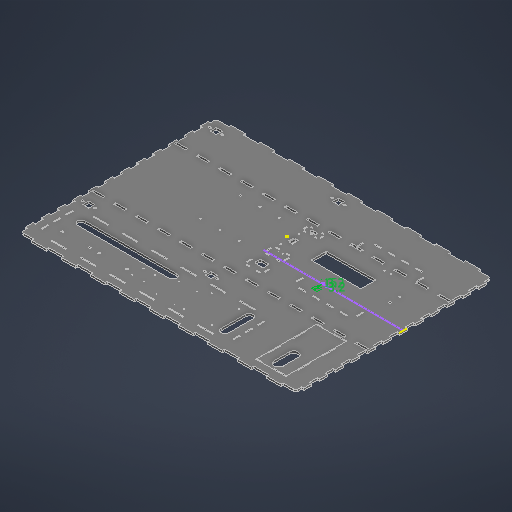
# Autodesk Inventor part: UpperBase
Saved by Autodesk Inventor 2027.1 (Build 311270010, 270A)
## iProperties
Created: 2026-09-29
Part Number: UpperBase
Material: MDF Medium Density Fiberboard
Document SubType Name: Modeling
Designer: SDS Scholar
Density: 0.8 g/cm^3
Appearance: Gray
Mass: 3254.36 g
Surface Area: 12239.4 cm^2
Volume: 4067.95 cm^3
Author: SDS Scholar
Autodesk Inventor part; units mm, degrees
(part 1 of 3)
ref_plane "YZ Plane" through (0, 0, 0) normal (1, 0, 0) x (0, 1, 0)
ref_plane "XZ Plane" through (0, 0, 0) normal (0, 1, 0) x (-1, 0, 0)
ref_plane "XY Plane" through (0, 0, 0) normal (0, 0, 1) x (1, 0, 0)
sketch "Sketch1" plane through (0, 0, 0) normal (0, 1, 0) x (-1, 0, 0)
  line L0 (456, 226) -> (-456, 226)
  line L1 (-456, 226) -> (-456, -226)
  line L2 (-456, -226) -> (456, -226)
  line L3 (456, -226) -> (456, 226)
  line L4 (0, 226) -> (0, -226) construction
  line L5 (456, 0) -> (-456, 0) construction
  line L6 (426, -196) -> (406, -196)
  line L7 (406, -196) -> (406, -176)
  line L8 (406, -176) -> (426, -176)
  line L9 (426, -176) -> (426, -196)
  line L10 (-24, -226) -> (-24, 226)
  line L11 (397.5, -186) -> (394.5, -186) construction
  line L12 (397.5, -183.1) -> (394.5, -183.1)
  line L13 (394.5, -188.9) -> (397.5, -188.9)
  arc A0 (397.5, -188.9) -> (397.5, -183.1) centre (397.5, -186) ccw
  arc A1 (394.5, -183.1) -> (394.5, -188.9) centre (394.5, -186) ccw
  line L14 (416, -196) -> (416, -176) construction
  line L15 (434.5, -186) -> (437.5, -186) construction
  line L16 (434.5, -183.1) -> (437.5, -183.1)
  line L17 (437.5, -188.9) -> (434.5, -188.9)
  arc A2 (434.5, -183.1) -> (434.5, -188.9) centre (434.5, -186) ccw
  arc A3 (437.5, -188.9) -> (437.5, -183.1) centre (437.5, -186) ccw
  line L18 (426, -186) -> (406, -186) construction
  line L19 (130, 226) -> (130, -226) construction
  line L20 (-24, -90) -> (126, -90)
  line L21 (126, -90) -> (126, 90)
  line L22 (126, 90) -> (-24, 90)
  line L23 (-24, 90) -> (-24, -90)
  circle A4 centre (41, 0) radius 25
  circle A5 centre (-34, 0) radius 25
  line L24 (456, 226) -> (-456, 226)
  line L25 (-456, 226) -> (-456, 426)
  line L26 (-456, 426) -> (456, 426)
  line L27 (456, 426) -> (456, 226)
  arc A6 (425.75, -196) -> (426, -195.75) centre (425.75, -195.75) ccw
  arc A7 (406, -195.75) -> (406.25, -196) centre (406.25, -195.75) ccw
  arc A8 (426, -176.25) -> (425.75, -176) centre (425.75, -176.25) ccw
  arc A9 (406.25, -176) -> (406, -176.25) centre (406.25, -176.25) ccw
  line L28 (406, 221) -> (406, 241)
  line L29 (406, 241) -> (426, 241)
  line L30 (426, 241) -> (426, 221)
  line L31 (397.5, 231) -> (394.5, 231) construction
  line L32 (397.5, 233.9) -> (394.5, 233.9)
  line L33 (394.5, 228.1) -> (397.5, 228.1)
  arc A10 (397.5, 228.1) -> (397.5, 233.9) centre (397.5, 231) ccw
  arc A11 (394.5, 233.9) -> (394.5, 228.1) centre (394.5, 231) ccw
  line L34 (416, 221) -> (416, 241) construction
  line L35 (426, 231) -> (406, 231) construction
  arc A12 (406.25, 241) -> (406, 240.75) centre (406.25, 240.75) ccw
  arc A13 (406, 221.25) -> (406.25, 221) centre (406.25, 221.25) ccw
  arc A14 (426, 240.75) -> (425.75, 241) centre (425.75, 240.75) ccw
  arc A15 (425.75, 221) -> (426, 221.25) centre (425.75, 221.25) ccw
  line L36 (434.5, 233.9) -> (437.5, 233.9)
  arc A16 (434.5, 233.9) -> (434.5, 228.1) centre (434.5, 231) ccw
  line L37 (434.5, 231) -> (437.5, 231) construction
  line L38 (437.5, 228.1) -> (434.5, 228.1)
  arc A17 (437.5, 228.1) -> (437.5, 233.9) centre (437.5, 231) ccw
  line L39 (426, 221) -> (406, 221)
  line L40 (6, -196) -> (6, -176)
  line L41 (6, -176) -> (26, -176)
  line L42 (26, -176) -> (26, -196)
  line L43 (-2.5, -186) -> (-5.5, -186) construction
  line L44 (-2.5, -183.1) -> (-5.5, -183.1)
  line L45 (-5.5, -188.9) -> (-2.5, -188.9)
  arc A18 (-2.5, -188.9) -> (-2.5, -183.1) centre (-2.5, -186) ccw
  arc A19 (-5.5, -183.1) -> (-5.5, -188.9) centre (-5.5, -186) ccw
  line L46 (16, -196) -> (16, -176) construction
  line L47 (26, -186) -> (6, -186) construction
  arc A20 (6.25, -176) -> (6, -176.25) centre (6.25, -176.25) ccw
  arc A21 (6, -195.75) -> (6.25, -196) centre (6.25, -195.75) ccw
  arc A22 (26, -176.25) -> (25.75, -176) centre (25.75, -176.25) ccw
  arc A23 (25.75, -196) -> (26, -195.75) centre (25.75, -195.75) ccw
  line L48 (34.5, -183.1) -> (37.5, -183.1)
  arc A24 (34.5, -183.1) -> (34.5, -188.9) centre (34.5, -186) ccw
  line L49 (34.5, -186) -> (37.5, -186) construction
  line L50 (37.5, -188.9) -> (34.5, -188.9)
  arc A25 (37.5, -188.9) -> (37.5, -183.1) centre (37.5, -186) ccw
  line L51 (26, -196) -> (6, -196)
  line L52 (6, 221) -> (6, 241)
  line L53 (6, 241) -> (26, 241)
  line L54 (26, 241) -> (26, 221)
  line L55 (-2.5, 231) -> (-5.5, 231) construction
  line L56 (-2.5, 233.9) -> (-5.5, 233.9)
  line L57 (-5.5, 228.1) -> (-2.5, 228.1)
  arc A26 (-2.5, 228.1) -> (-2.5, 233.9) centre (-2.5, 231) ccw
  arc A27 (-5.5, 233.9) -> (-5.5, 228.1) centre (-5.5, 231) ccw
  line L58 (16, 221) -> (16, 241) construction
  line L59 (26, 231) -> (6, 231) construction
  arc A28 (6.25, 241) -> (6, 240.75) centre (6.25, 240.75) ccw
  arc A29 (6, 221.25) -> (6.25, 221) centre (6.25, 221.25) ccw
  arc A30 (26, 240.75) -> (25.75, 241) centre (25.75, 240.75) ccw
  arc A31 (25.75, 221) -> (26, 221.25) centre (25.75, 221.25) ccw
  line L60 (34.5, 233.9) -> (37.5, 233.9)
  arc A32 (34.5, 233.9) -> (34.5, 228.1) centre (34.5, 231) ccw
  line L61 (34.5, 231) -> (37.5, 231) construction
  line L62 (37.5, 228.1) -> (34.5, 228.1)
  arc A33 (37.5, 228.1) -> (37.5, 233.9) centre (37.5, 231) ccw
  line L63 (26, 221) -> (6, 221)
  line L64 (426, 396) -> (-204, 396)
  line L65 (-204, 396) -> (-204, 256)
  line L66 (-204, 256) -> (426, 256)
  line L67 (426, 256) -> (426, 396)
  line L68 (423, 393) -> (-201, 393)
  line L69 (-201, 393) -> (-201, 259)
  line L70 (-201, 259) -> (423, 259)
  line L71 (423, 259) -> (423, 393)
  line L72 (-396, 396) -> (-296, 396)
  line L73 (-296, 396) -> (-296, 196)
  line L74 (-296, 196) -> (-396, 196)
  line L75 (-396, 196) -> (-396, 396)
  line L76 (-299, 199) -> (-299, 393)
  line L77 (-299, 393) -> (-393, 393)
  line L78 (-393, 393) -> (-393, 199)
  line L79 (-393, 199) -> (-299, 199)
  circle A34 centre (-115, 0) radius 2.5
  circle A35 centre (-258, 0) radius 2.5
  line L80 (-34, 25) -> (-34, -25) construction
  line L81 (-4, 45) -> (-64, 45)
  line L82 (-64, 45) -> (-64, 145)
  line L83 (-64, 145) -> (-4, 145)
  line L84 (-4, 145) -> (-4, 45)
  line L85 (-4, 142) -> (-64, 142) construction
  line L86 (-7, 145) -> (-7, 45) construction
  line L87 (-61, 145) -> (-61, 45) construction
  line L88 (-34, 45) -> (-34, 145) construction
  line L89 (-4, 95) -> (-64, 95) construction
  line L90 (-26.5, 45) -> (-41.5, 45)
  line L91 (-41.5, 45) -> (-41.5, 48)
  line L92 (-41.5, 48) -> (-26.5, 48)
  line L93 (-26.5, 48) -> (-26.5, 45)
  line L94 (-26.5, 48) -> (-7, 48) construction
  line L95 (-11.75, 45) -> (-21.75, 45)
  line L96 (-21.75, 45) -> (-21.75, 48)
  line L97 (-21.75, 48) -> (-11.75, 48)
  line L98 (-11.75, 48) -> (-11.75, 45)
  line L99 (-4, 78) -> (-61, 78) construction
  line L100 (-4, 81) -> (-61, 81) construction
  line L101 (-11.75, 78) -> (-21.75, 78)
  line L102 (-21.75, 78) -> (-21.75, 81)
  line L103 (-21.75, 81) -> (-11.75, 81)
  line L104 (-11.75, 81) -> (-11.75, 78)
  line L105 (-11.75, 142) -> (-21.75, 142)
  line L106 (-21.75, 142) -> (-21.75, 145)
  line L107 (-21.75, 145) -> (-11.75, 145)
  line L108 (-11.75, 145) -> (-11.75, 142)
  line L109 (-4, 55.5) -> (-7, 55.5)
  line L110 (-7, 55.5) -> (-7, 70.5)
  line L111 (-7, 70.5) -> (-4, 70.5)
  line L112 (-4, 70.5) -> (-4, 55.5)
  line L113 (-7, 45) -> (-7, 145) construction
  line L114 (-4, 134.5) -> (-7, 134.5)
  line L115 (-7, 134.5) -> (-7, 119.5)
  line L116 (-7, 119.5) -> (-4, 119.5)
  line L117 (-46.25, 45) -> (-46.25, 48)
  line L118 (-46.25, 48) -> (-56.25, 48)
  line L119 (-56.25, 48) -> (-56.25, 45)
  line L120 (-56.25, 78) -> (-46.25, 78)
  line L121 (-46.25, 78) -> (-46.25, 81)
  line L122 (-46.25, 81) -> (-56.25, 81)
  line L123 (-56.25, 81) -> (-56.25, 78)
  line L124 (-56.25, 142) -> (-46.25, 142)
  line L125 (-46.25, 142) -> (-46.25, 145)
  line L126 (-56.25, 145) -> (-56.25, 142)
  line L127 (-64, 55.5) -> (-61, 55.5)
  line L128 (-61, 55.5) -> (-61, 70.5)
  line L129 (-61, 70.5) -> (-64, 70.5)
  line L130 (-61, 119.5) -> (-64, 119.5)
  line L131 (-61, 134.5) -> (-61, 119.5)
  line L132 (-64, 134.5) -> (-61, 134.5)
  line L133 (-24, 125) -> (-44, 125)
  line L134 (-49, 120) -> (-49, 110)
  line L135 (-44, 105) -> (-24, 105)
  line L136 (-19, 110) -> (-19, 120)
  arc A36 (-19, 120) -> (-24, 125) centre (-24, 120) ccw
  arc A37 (-24, 105) -> (-19, 110) centre (-24, 110) ccw
  arc A38 (-49, 110) -> (-44, 105) centre (-44, 110) ccw
  arc A39 (-44, 125) -> (-49, 120) centre (-44, 120) ccw
  line L137 (-6, -45) -> (-62, -45)
  line L138 (-62, -45) -> (-62, -71)
  line L139 (-62, -71) -> (-6, -71)
  line L140 (-6, -71) -> (-6, -45)
  line L141 (-3, -45) -> (-59, -45)
  line L142 (-59, -45) -> (-59, -71)
  line L143 (-59, -71) -> (-3, -71)
  line L144 (-3, -71) -> (-3, -45)
  line L145 (-59, -53) -> (-56, -53)
  line L146 (-56, -53) -> (-56, -63)
  line L147 (-56, -63) -> (-59, -63)
  line L148 (-59, -63) -> (-59, -53)
  line L149 (-31, -45) -> (-31, -71) construction
  line L150 (-51.5, -45) -> (-46.5, -45)
  line L151 (-46.5, -45) -> (-46.5, -48)
  line L152 (-46.5, -48) -> (-51.5, -48)
  line L153 (-51.5, -48) -> (-51.5, -45)
  line L154 (-46.5, -71) -> (-51.5, -71)
  line L155 (-51.5, -71) -> (-51.5, -68)
  line L156 (-51.5, -68) -> (-46.5, -68)
  line L157 (-46.5, -68) -> (-46.5, -71)
  line L158 (-15.5, -45) -> (-15.5, -48)
  line L159 (-15.5, -48) -> (-10.5, -48)
  line L160 (-10.5, -48) -> (-10.5, -45)
  line L161 (-15.5, -68) -> (-15.5, -71)
  line L162 (-10.5, -68) -> (-15.5, -68)
  line L163 (-10.5, -71) -> (-10.5, -68)
  line L164 (-6, -63) -> (-3, -63)
  line L165 (-3, -53) -> (-6, -53)
  line L166 (-6, -53) -> (-6, -63)
  line L167 (-34, -71) -> (-34, -45) construction
  line L168 (-25, -62) -> (-37, -62)
  line L169 (-37, -54) -> (-25, -54)
  arc A40 (-25, -62) -> (-21, -58) centre (-25, -58) ccw
  arc A41 (-21, -58) -> (-25, -54) centre (-25, -58) ccw
  arc A42 (-37, -54) -> (-41, -58) centre (-37, -58) ccw
  arc A43 (-41, -58) -> (-37, -62) centre (-37, -58) ccw
  circle A44 centre (-27.09, 53.5) radius 1.25
  circle A45 centre (-40.91, 53.5) radius 1.25
  line L170 (-29, -51) -> (-33, -51)
  line L171 (-33, -51) -> (-33, -48)
  line L172 (-33, -48) -> (-29, -48)
  line L173 (-29, -48) -> (-29, -51)
  circle A46 centre (193, 88) radius 2.5
  circle A47 centre (193, -43) radius 2.5
  circle A48 centre (130, 88) radius 2.5
  circle A49 centre (130, -43) radius 2.5
  circle A50 centre (67, 88) radius 2.5
  circle A51 centre (67, -43) radius 2.5
  line L174 (193, 88) -> (193, -43) construction
  line L175 (416, 231) -> (416, -186) construction
  line L176 (-115, 0) -> (-131, 0) construction
  line L177 (-115, 10) -> (-242, 10)
  line L178 (-242, -10) -> (-115, -10)
  arc A52 (-115, -10) -> (-115, 10) centre (-115, 0) ccw
  arc A53 (-131, 10) -> (-131, -10) centre (-131, 0) ccw
  line L179 (-258, 0) -> (-242, 0) construction
  line L180 (-258, -10) -> (-242, -10)
  line L181 (-242, 10) -> (-258, 10)
  arc A54 (-258, 10) -> (-258, -10) centre (-258, 0) ccw
  arc A55 (-242, -10) -> (-242, 10) centre (-242, 0) ccw
  line L182 (423, 259) -> (375, 259)
  line L183 (375, 259) -> (375, 256)
  line L184 (375, 256) -> (423, 256)
  line L185 (423, 256) -> (423, 259)
  line L186 (327, 259) -> (327, 256)
  line L187 (279, 259) -> (279, 256)
  line L188 (231, 259) -> (231, 256)
  line L189 (183, 259) -> (183, 256)
  line L190 (135, 259) -> (135, 256)
  line L191 (87, 259) -> (87, 256)
  line L192 (39, 259) -> (39, 256)
  line L193 (-9, 259) -> (-9, 256)
  line L194 (-57, 259) -> (-57, 256)
  line L195 (-105, 259) -> (-105, 256)
  line L196 (-153, 259) -> (-153, 256)
  line L197 (-201, 259) -> (-201, 256)
  line L198 (-201, 393) -> (-153, 393)
  line L199 (-153, 393) -> (-153, 396)
  line L200 (-153, 396) -> (-201, 396)
  line L201 (-201, 396) -> (-201, 393)
  line L202 (-105, 393) -> (-105, 396)
  line L203 (-57, 393) -> (-57, 396)
  line L204 (-9, 393) -> (-9, 396)
  line L205 (39, 393) -> (39, 396)
  line L206 (87, 393) -> (87, 396)
  line L207 (135, 393) -> (135, 396)
  line L208 (426, 396) -> (423, 396)
  line L209 (423, 396) -> (423, 376)
  line L210 (423, 376) -> (426, 376)
  line L211 (426, 376) -> (426, 396)
  line L212 (423, 356) -> (426, 356)
  line L213 (423, 336) -> (426, 336)
  line L214 (423, 316) -> (426, 316)
  line L215 (423, 296) -> (426, 296)
  line L216 (423, 276) -> (426, 276)
  line L217 (423, 256) -> (426, 256)
  line L218 (-204, 396) -> (-201, 396)
  line L219 (-201, 396) -> (-201, 376)
  line L220 (-201, 376) -> (-204, 376)
  line L221 (-204, 376) -> (-204, 396)
  line L222 (-201, 356) -> (-204, 356)
  line L223 (-201, 336) -> (-204, 336)
  line L224 (-201, 316) -> (-204, 316)
  line L225 (-201, 296) -> (-204, 296)
  line L226 (-201, 276) -> (-204, 276)
  line L227 (-201, 256) -> (-204, 256)
  line L228 (183, 393) -> (183, 396)
  line L229 (231, 393) -> (231, 396)
  line L230 (279, 393) -> (279, 396)
  line L231 (327, 393) -> (327, 396)
  line L232 (375, 393) -> (375, 396)
  line L233 (423, 393) -> (423, 396)
  line L234 (-393.0285, 198.9955) -> (-299.0285, 198.9955)
  line L235 (-296.0285, 195.9955) -> (-396.0285, 195.9955)
  line L236 (-296.0285, 395.9955) -> (-296.0285, 195.9955)
  line L237 (-299.0285, 198.9955) -> (-299.0285, 392.9955)
  line L238 (-396.0285, 195.9955) -> (-396.0285, 395.9955)
  line L239 (-393.0285, 392.9955) -> (-393.0285, 198.9955)
  line L240 (-299.0285, 392.9955) -> (-393.0285, 392.9955)
  line L241 (-396.0285, 395.9955) -> (-296.0285, 395.9955)
  line L242 (-396.0285, 195.9955) -> (-393.0285, 195.9955)
  line L243 (-393.0285, 195.9955) -> (-393.0285, 236.2955)
  line L244 (-393.0285, 236.2955) -> (-396.0285, 236.2955)
  line L245 (-396.0285, 236.2955) -> (-396.0285, 195.9955)
  line L246 (-393.0285, 236.2955) -> (-396.0285, 236.2955)
  line L247 (-396.0285, 236.2955) -> (-396.0285, 276.2955)
  line L248 (-396.0285, 276.2955) -> (-393.0285, 276.2955)
  line L249 (-393.0285, 276.2955) -> (-393.0285, 236.2955)
  line L250 (-393.0285, 276.2955) -> (-396.0285, 276.2955)
  line L251 (-396.0285, 276.2955) -> (-396.0285, 316.5955)
  line L252 (-396.0285, 316.5955) -> (-393.0285, 316.5955)
  line L253 (-393.0285, 316.5955) -> (-393.0285, 276.2955)
  line L254 (-393.0285, 316.5955) -> (-396.0285, 316.5955)
  line L255 (-396.0285, 316.5955) -> (-396.0285, 356.5955)
  line L256 (-396.0285, 356.5955) -> (-393.0285, 356.5955)
  line L257 (-393.0285, 356.5955) -> (-393.0285, 316.5955)
  line L258 (-393.0285, 356.5955) -> (-396.0285, 356.5955)
  line L259 (-396.0285, 356.5955) -> (-396.0285, 395.9955)
  line L260 (-396.0285, 395.9955) -> (-393.0285, 395.9955)
  line L261 (-393.0285, 395.9955) -> (-393.0285, 356.5955)
  line L262 (-393.0285, 395.9955) -> (-353.0285, 395.9955)
  line L263 (-353.0285, 395.9955) -> (-353.0285, 392.9955)
  line L264 (-353.0285, 392.9955) -> (-393.0285, 392.9955)
  line L265 (-393.0285, 392.9955) -> (-393.0285, 395.9955)
  line L266 (-353.0285, 392.9955) -> (-312.7285, 392.9955)
  line L267 (-312.7285, 392.9955) -> (-312.7285, 395.9955)
  line L268 (-312.7285, 395.9955) -> (-353.0285, 395.9955)
  line L269 (-353.0285, 395.9955) -> (-353.0285, 392.9955)
  line L270 (-299.0285, 392.9955) -> (-312.7285, 392.9955)
  line L271 (-312.7285, 392.9955) -> (-312.7285, 395.9955)
  line L272 (-312.7285, 395.9955) -> (-299.0285, 395.9955)
  line L273 (-299.0285, 395.9955) -> (-299.0285, 392.9955)
  line L274 (-296.0285, 395.9955) -> (-299.0285, 395.9955)
  line L275 (-299.0285, 395.9955) -> (-299.0285, 355.6955)
  line L276 (-296.0285, 355.6955) -> (-296.0285, 395.9955)
  line L277 (-296.0285, 195.9955) -> (-299.0285, 195.9955)
  line L278 (-299.0285, 195.9955) -> (-299.0285, 236.2955)
  line L279 (-299.0285, 236.2955) -> (-296.0285, 236.2955)
  line L280 (-296.0285, 236.2955) -> (-296.0285, 195.9955)
  line L281 (-296.0285, 236.2955) -> (-299.0285, 236.2955)
  line L282 (-299.0285, 236.2955) -> (-299.0285, 276.2955)
  line L283 (-299.0285, 276.2955) -> (-296.0285, 276.2955)
  line L284 (-296.0285, 276.2955) -> (-296.0285, 236.2955)
  line L285 (-296.0285, 276.2955) -> (-299.0285, 276.2955)
  line L286 (-299.0285, 276.2955) -> (-299.0285, 316.5955)
  line L287 (-299.0285, 316.5955) -> (-296.0285, 316.5955)
  line L288 (-296.0285, 316.5955) -> (-296.0285, 276.2955)
  line L289 (-296.0285, 316.5955) -> (-299.0285, 316.5955)
  line L290 (-299.0285, 316.5955) -> (-299.0285, 356.5955)
  line L291 (-299.0285, 356.5955) -> (-296.0285, 356.5955)
  line L292 (-296.0285, 356.5955) -> (-296.0285, 316.5955)
  line L293 (-393.0285, 195.9955) -> (-353.0285, 195.9955)
  line L294 (-353.0285, 195.9955) -> (-353.0285, 198.9955)
  line L295 (-353.0285, 198.9955) -> (-393.0285, 198.9955)
  line L296 (-393.0285, 198.9955) -> (-393.0285, 195.9955)
  line L297 (-353.0285, 198.9955) -> (-312.7285, 198.9955)
  line L298 (-312.7285, 198.9955) -> (-312.7285, 195.9955)
  line L299 (-312.7285, 195.9955) -> (-353.0285, 195.9955)
  line L300 (-353.0285, 195.9955) -> (-353.0285, 198.9955)
  point P0 (0, 0)
  point P1 (-24, 0)
  point P2 (396, -186)
  point P3 (436, -186)
  point P4 (130, 0)
  point P5 (126, 0)
  point P6 (0, 0)
  point P7 (-456, 226)
  point P8 (396, 231)
  point P9 (436, 231)
  point P10 (-4, -186)
  point P11 (16, -186)
  point P12 (36, -186)
  point P13 (-4, 231)
  point P14 (16, 231)
  point P15 (36, 231)
  point P16 (6.25, 221)
  point P17 (25.75, 241)
  point P18 (6.25, 241)
  point P19 (6.25, -196)
  point P20 (25.75, -176)
  point P21 (6.25, -176)
  point P22 (-396, 226)
  point P23 (-393, 226)
  point P24 (-299, 226)
  point P25 (-296, 226)
  point P26 (-284.8127, -574.8692)
  point P27 (-284.8127, -584.8692)
  point P28 (-284.8127, -612.3692)
  point P29 (-284.8127, -622.3692)
  point P30 (-274.3127, -631.6192)
  point P31 (-274.3127, -628.6192)
  point P32 (-259.3127, -628.6192)
  point P33 (-259.3127, -631.6192)
  point P34 (-210.3127, -631.6192)
  point P35 (-210.3127, -628.6192)
  point P36 (-195.3127, -628.6192)
  point P37 (-195.3127, -631.6192)
  point P38 (-184.8127, -622.3692)
  point P39 (-184.8127, -612.3692)
  point P40 (-184.8127, -584.8692)
  point P41 (-184.8127, -574.8692)
  point P42 (-195.3127, -565.6192)
  point P43 (-195.3127, -568.6192)
  point P44 (-210.3127, -568.6192)
  point P45 (-210.3127, -565.6192)
  point P46 (-259.3127, -565.6192)
  point P47 (-259.3127, -568.6192)
  point P48 (-274.3127, -568.6192)
  point P49 (-274.3127, -565.6192)
  point P50 (-34, 95)
  point P51 (-34, 48)
  point P52 (-34, 95)
  point P53 (-16.75, 48)
  point P54 (-16.75, 48)
  point P55 (-16.75, 78)
  point P56 (-16.75, 142)
  point P57 (-4, 63)
  point P58 (-4, 119.5)
  point P59 (-4, 134.5)
  point P60 (-64, 134.5)
  point P61 (-64, 119.5)
  point P62 (-46.25, 145)
  point P63 (-56.25, 145)
  point P64 (-11.75, 145)
  point P65 (-64, 70.5)
  point P66 (-64, 55.5)
  point P67 (-4, 70.5)
  point P68 (-21.75, 45)
  point P69 (-56.25, 45)
  point P70 (-46.25, 45)
  point P71 (-19, 125)
  point P72 (-49, 105)
  point P73 (-19, 105)
  point P74 (-34, 105)
  point P75 (-3, -58)
  point P76 (-56, -58)
  point P77 (-59, -58)
  point P78 (-49, -48)
  point P79 (-49, -68)
  point P80 (-292.5225, -73.6896)
  point P81 (-285.0225, -81.6896)
  point P82 (-249.0225, -81.6896)
  point P83 (-244.0225, -81.6896)
  point P84 (-236.5225, -73.6896)
  point P85 (-236.5225, -63.6896)
  point P86 (-244.0225, -55.6896)
  point P87 (-249.0225, -55.6896)
  point P88 (-280.0225, -55.6896)
  point P89 (-46.5, -45)
  point P90 (-51.5, -45)
  point P91 (-234, -46)
  point P92 (-234, -56)
  point P93 (-51.5, -71)
  point P94 (-46.5, -71)
  point P95 (-10.5, -45)
  point P96 (-15.5, -45)
  point P97 (-6, -63)
  point P98 (-6, -53)
  point P99 (-15.5, -71)
  point P100 (-10.5, -71)
  point P101 (-21, -62)
  point P102 (-41, -54)
  point P103 (-21, -54)
  point P104 (-6, -58)
  point P105 (-31, -54)
  point P106 (-21, -58)
  point P107 (-31, -48)
  point P108 (-34, -58)
  point P109 (-31, -58)
  point P110 (-6, -58)
  point P111 (-31, -51)
  point P112 (-3, -53)
  point P113 (-3, -63)
  point P114 (416, 22.5)
  point P115 (193, 22.5)
  point P116 (-123, 0)
  point P117 (-250, 0)
  point P118 (-396, 395.9955)
  point P119 (-396, 356.5955)
  point P120 (-396, 316.5955)
  point P121 (-396, 276.2955)
  point P122 (-396, 236.2955)
  point P123 (-393.0285, 196)
  point P124 (-353.0285, 196)
  point P125 (-312.7285, 196)
  point P126 (-299.0285, 196)
  point P127 (-299.0285, 199)
  point P128 (-353.0285, 393)
  point P129 (-312.7285, 393)
  point P130 (-299.0285, 393)
  point P131 (-299, 356.5955)
  point P132 (-299, 316.5955)
  point P133 (-299, 276.2955)
  point P134 (-299, 236.2955)
  point P135 (-296.0285, 196)
  dimension "d1" = 912
  dimension "d15" = 20
  dimension "d16" = 20
  dimension "d17" = 30
  dimension "d18" = 30
  dimension "d26" = 1.5
  dimension "d27" = 5.8
  dimension "d28" = 8.5
  dimension "d51" = 480
  dimension "d52" = 326
  dimension "d72" = 150
  dimension "d73" = 180
  dimension "d74" = 50
  dimension "d75" = 85
  dimension "d78" = 50
  dimension "d79" = 75
  dimension "d80" = 652
  dimension "d81" = 200
  dimension "d82" = 912
  dimension "d85" = 0.25
  dimension "d88" = 417
  dimension "d91" = 400
  dimension "d94" = 140
  dimension "d95" = 630
  dimension "d96" = 30
  dimension "d97" = 30
  dimension "d98" = 3
  dimension "d104" = 200
  dimension "d105" = 100
  dimension "d106" = 30
  dimension "d107" = 60
  dimension "d108" = 3
  dimension "d110" = 81
  dimension "d111" = 5
  dimension "d112" = 5
  dimension "d119" = 100
  dimension "d120" = 60
  dimension "d121" = 45
  dimension "d123" = 3
  dimension "d124" = 3
  dimension "d125" = 3
  dimension "d151" = 3
  dimension "d152" = 15
  dimension "d153" = 10
  dimension "d154" = 3
  dimension "d155" = 30
  dimension "d156" = 10
  dimension "d157" = 10
  dimension "d158" = 15
  dimension "d159" = 18
  dimension "d160" = 30
  dimension "d161" = 20
  dimension "d162" = 20
  dimension "d163" = 5
  dimension "d164" = 56
  dimension "d165" = 26
  dimension "d166" = 90
  dimension "d167" = 56
  dimension "d168" = 26
  dimension "d169" = 10
  dimension "d170" = 3
  dimension "d171" = 5
  dimension "d172" = 3
  dimension "d173" = 10
  constraints: 622 end point, 90 point on circle, 87 parallel, 71 point on line, 56 centre point, 55 symmetric about line, 49 perpendicular, 48 midpoint, 45 horizontal, 26 tangent, 8 vertical, 8 vertical alignment, 7 horizontal alignment, 6 equal radius, 1 coincident, 308 other
  measures "d1" distance of L1.end L2.end
  measures "d15" distance of L7.end L8.end
  measures "d16" distance of L6.end L7.end
  measures "d17" distance between parallel lines of L2 L6
  measures "d18" distance between parallel lines of L3 L9
  measures "d26" distance of point (396, -186) L11.end
  measures "d27" diameter of A1
  measures "d28" distance from line of L7 L11.start
  measures "d51" distance between parallel lines of L3 L10
  measures "d52" distance between parallel lines of L3 L19
  measures "d72" distance of L21.end L22.end
  measures "d73" distance of L20.end L21.end
  measures "d74" diameter of A4
  measures "d75" distance from line of L21 A4.centre
  measures "d78" diameter of A5
  measures "d79" distance of A5.centre A4.centre
  measures "d80" distance between parallel lines of L26 L2
  measures "d81" distance between parallel lines of L26 L0
  measures "d82" distance of L25.end L26.end
  measures "d85" radius of A6
  measures "d88" distance of L7.end L28.end
  measures "d91" distance of L7.end L40.end
  measures "d94" distance of L66.end L64.start
  measures "d95" distance of L65.end L66.end
  measures "d96" distance between parallel lines of L26 L64
  measures "d97" distance between parallel lines of L27 L67
  measures "d98" distance between parallel lines of L67 L71
  measures "d104" distance of L72.end L73.end
  measures "d105" distance of L73.end L74.end
  measures "d106" distance between parallel lines of L26 L72
  measures "d107" distance between parallel lines of L25 L75
  measures "d108" distance between parallel lines of L73 L76
  measures "d110" distance of A5.centre L176.start
  measures "d111" diameter of A34
  measures "d112" diameter of A35
  measures "d119" distance of L83.end L81.start
  measures "d120" distance of L81.start L81.end
  measures "d121" distance from line of L81 A5.centre
  measures "d123" distance between parallel lines of L84 L86
  measures "d124" distance between parallel lines of L83 L85
  measures "d125" distance between parallel lines of L82 L87
  measures "d151" distance of L92.end L90.start
  measures "d152" distance of L91.end L92.end
  measures "d153" distance of L96.end L97.end
  measures "d154" distance between parallel lines of L99 L100
  measures "d155" distance between parallel lines of L94 L99
  measures "d156" distance of L101.start L101.end
  measures "d157" distance of L105.start L105.end
  measures "d158" distance of L109.end L110.end
  measures "d159" distance from line of L81 point (-4, 63)
  measures "d160" distance of point (-49, 105) point (-19, 105)
  measures "d161" distance of point (-19, 105) point (-19, 125)
  measures "d162" distance between parallel lines of L133 L83
  measures "d163" radius of A36
  measures "d164" distance of L137.start L137.end
  measures "d165" distance of L137.end L138.end
  measures "d166" distance between parallel lines of L81 L137
  measures "d167" distance of L141.start L141.end
  measures "d168" distance of L141.end L142.end
  measures "d169" distance of L145.end L146.end
  measures "d170" distance of L145.start L145.end
  measures "d171" distance of L151.end L152.end
  measures "d172" distance of L152.end L150.start
  measures "d173" distance from line of L142 point (-49, -48)
extrude "Extrusion1" add sketch "Sketch1" along normal blind 7 contours L3 L2 L10 L20 L21 L22 A50 L84 L83 L0 L52 L63 L54 L28 L39 L30 | L0 L30 L29 L28 L54 L53 L52 L73 L72 L75 L241 L238 L25 L26 L27 | L30 A15 L39 A13 L28 L0 | L0 L28 A12 L29 A14 L30 | A14 L29 L30 | L30 L39 A15 | L2 L1 L0 L238 L235 L236 L74 L73 L10 L83 L82 L81 A5 L137 L138 L139 | L54 A31 L63 A29 L52 L0 | L0 L52 A28 L53 A30 L54 | A13 L39 L28 | L28 L29 A12 | L10 L139 L143 L144 L141 L137 A5 L81 L84 L22 A50 L21 L20 | A30 L53 L54 | L54 L63 A31 | L139 L157 L156 L155 L142 L147 L146 L145 L137 L153 L152 L151 L10 A41 L169 A42 A43 L168 A40 | L10 A40 A41 L137 L158 L159 L160 L140 L139 L163 L162 L161 | L238 L244 L75 L0 | L0 L75 L74 L243 L235 L238 | A29 L63 L52 | L52 L53 A28 | A40 L168 A43 A42 L169 A41 L10 | L10 A41 A40 | L139 L155 L156 L157 | L161 L162 L163 L139 | L75 L244 L239 L0 | L0 L239 L243 L74 L75 | L238 L248 L75 L244 | L73 L74 L236 L0 | L0 L236 L241 L75 L72 L73 | L83 L106 L105 L108 L84 L114 L115 L116 L22 L10 A37 L136 A36 | L10 L133 A39 L134 A38 L135 L81 L93 L92 L91 L117 L118 L119 L82 L127 L128 L129 L130 L131 L132 L83 L126 L124 L125 | A50 L22 | L22 A50 | L239 L240 L78 L0 | L0 L78 L79 L237 L234 L239 | L75 L248 L239 L244 | L243 L74 L294 L235 | L238 L252 L75 L248 | L236 L74 L278 L237 L79 L76 L0 | L0 L76 L279 L236 | A36 L136 A37 L10 | L10 L135 A38 L134 A39 L133 | L125 L124 L126 L83 | L83 L108 L105 L106 | L139 L138 L137 L142 | L140 L164 L144 L143 | L78 L240 L237 L0 | L0 L237 L79 L78 | L234 L294 L74 L243 | L75 L252 L239 L248 | L294 L74 L298 L235 | L238 L256 L75 L252 | L76 L79 L237 L0 | L0 L237 L279 L76 | L279 L76 L283 L236 | L236 L235 L278 L74 | A5 L10 | L10 A5 | L137 L160 L159 L158 | L151 L152 L153 L137 | L142 L145 L146 L147 | L140 L165 L144 L164 | L84 L111 L110 L109 L81 L98 L97 L96 L10 L22 | L240 L261 L241 L263 L77 L78 | L78 L77 L263 L240 | L234 L298 L74 L294 | L75 L256 L239 L252 | L298 L74 L278 L235 | L238 L241 L75 L256 | L279 L237 L283 L76 | L283 L76 L287 L236 | L74 L298 L234 L278 | L241 L261 L239 L256 L75 | L140 L141 L144 L165 | L116 L115 L114 L84 | L84 L109 L110 L111 | L263 L77 L267 L240 | L283 L237 L287 L76 | L287 L76 L291 L236 | L132 L131 L130 L82 | L263 L241 L267 L77 | L267 L77 L273 L240 | L287 L237 L291 L76 | L96 L97 L98 L81 | L81 L91 L92 L93 | L267 L241 L273 L77 | L273 L77 L76 L291 L237 | L76 L77 L273 L241 L236 L291 | L129 L128 L127 L82 | L81 L119 L118 L117 | L6 A6 L9 | L6 A7 L7 A9 L8 A8 L9 A6 | L6 L7 A7 | A8 L8 L9 | L7 L8 A9 | A0 L13 A1 L12 | L16 A3 L17 A2 | A4 | A10 L33 A11 L32 | L36 A17 L38 A16 | L40 A21 L51 | L40 A20 L41 A22 L42 A23 L51 A21 | L40 L41 A20 | A23 L42 L51 | L41 L42 A22 | A18 L45 A19 L44 | L48 A25 L50 A24 | A26 L57 A27 L56 | L60 A33 L62 A32 | L67 L210 L71 L209 L64 | L209 L68 L232 L64 | L67 L212 L71 L210 | L232 L68 L231 L64 | L71 L70 L69 L68 | L67 L213 L71 L212 | L231 L68 L230 L64 | L67 L214 L71 L213 | L230 L68 L229 L64 | L67 L215 L71 L214 | L229 L68 L228 L64 | L67 L216 L71 L215 | L228 L68 L207 L64 | L67 L66 L185 L71 L216 | L207 L68 L206 L64 | L206 L68 L205 L64 | L66 L183 L70 L185 | L205 L68 L204 L64 | L66 L186 L70 L183 | L204 L68 L203 L64 | L66 L187 L70 L186 | L203 L68 L202 L64 | L66 L188 L70 L187 | L202 L68 L199 L64 | L66 L189 L70 L188 | L199 L68 L201 L64 | L66 L190 L70 L189 | L201 L69 L220 L65 L64 | L66 L191 L70 L190 | L66 L192 L70 L191 | L220 L69 L222 L65 | L66 L193 L70 L192 | L222 L69 L223 L65 | L66 L194 L70 L193 | L223 L69 L224 L65 | L66 L195 L70 L194 | L224 L69 L225 L65 | L66 L196 L70 L195 | L225 L69 L226 L65 | L66 L197 L70 L196 | L226 L69 L197 L66 L65 | A34 | A35 | L101 L102 L103 L104 | L123 L122 L121 L120 | A44 | A45 | L170 L171 L172 L173 | A46 | A47 | A48 | A49 | A51 | A52 L178 A53 L177 | A53 L178 A55 L177 | A55 L180 A54 L181
extrude "Extrusion2" cut sketch "Sketch1" along normal blind 7 contours L30 A15 L39 A13 L28 L0 | L0 L28 A12 L29 A14 L30 | L54 A31 L63 A29 L52 L0 | L0 L52 A28 L53 A30 L54 | A40 L168 A43 A42 L169 A41 L10 | L10 A41 A40 | L139 L155 L156 L157 | L161 L162 L163 L139 | L73 L74 L236 L0 | L0 L236 L241 L75 L72 L73 | A50 L22 | L22 A50 | L239 L240 L78 L0 | L0 L78 L79 L237 L234 L239 | L75 L248 L239 L244 | A36 L136 A37 L10 | L10 L135 A38 L134 A39 L133 | L125 L124 L126 L83 | L83 L108 L105 L106 | L234 L294 L74 L243 | L279 L76 L283 L236 | L137 L160 L159 L158 | L151 L152 L153 L137 | L142 L145 L146 L147 | L140 L165 L144 L164 | L240 L261 L241 L263 L77 L78 | L75 L256 L239 L252 | L74 L298 L234 L278 | L116 L115 L114 L84 | L84 L109 L110 L111 | L287 L76 L291 L236 | L132 L131 L130 L82 | L96 L97 L98 L81 | L267 L241 L273 L77 | L129 L128 L127 L82 | L81 L119 L118 L117 | L6 A7 L7 A9 L8 A8 L9 A6 | A0 L13 A1 L12 | L16 A3 L17 A2 | A10 L33 A11 L32 | L36 A17 L38 A16 | L40 A20 L41 A22 L42 A23 L51 A21 | A18 L45 A19 L44 | L48 A25 L50 A24 | A26 L57 A27 L56 | L60 A33 L62 A32 | L67 L212 L71 L210 | L232 L68 L231 L64 | L67 L214 L71 L213 | L230 L68 L229 L64 | L67 L216 L71 L215 | L228 L68 L207 L64 | L206 L68 L205 L64 | L66 L186 L70 L183 | L204 L68 L203 L64 | L66 L188 L70 L187 | L202 L68 L199 L64 | L66 L190 L70 L189 | L66 L192 L70 L191 | L220 L69 L222 L65 | L66 L194 L70 L193 | L223 L69 L224 L65 | L66 L196 L70 L195 | L225 L69 L226 L65 | A34 | A35 | L101 L102 L103 L104 | L123 L122 L121 L120 | A44 | A45 | L170 L171 L172 L173 | A46 | A47 | A48 | A49 | A51 | A52 L178 A53 L177 | A53 L178 A55 L177 | A55 L180 A54 L181
fillet "Fillet1" radius 7 4 edges at (456, 3.5, 426) (456, 3.5, -226) (-456, 3.5, -226) (-456, 3.5, 426)
sketch "Sketch2" plane through (0, 7, 0) normal (0, 1, 0) x (1, 0, 0)
  line L0 (456, -419) -> (456, 219) projected
  line L1 (456, 16) -> (354.8, 16)
  line L2 (354.8, 16) -> (354.8, -16)
  line L3 (354.8, -16) -> (456, -16)
  line L4 (456, -16) -> (456, 16)
  line L5 (306.8, 0) -> (356.4612, 0)
  circle A0 centre (354.8, -16) radius 2.9
  circle A1 centre (354.8, 16) radius 2.9
  circle A2 centre (162.2, -16) radius 2.9
  circle A3 centre (162.2, 16) radius 2.9
  point P0 (0, 0)
  point P1 (354.8, 0)
  dimension "d205" = 101.2
  dimension "d206" = 32
  dimension "d208" = 5.8
  dimension "d209" = 5.8
  dimension "d212" = 192.6
  dimension "d403" = 48
  dimension "d404" = 203
  dimension "d405" = 99.5388
  constraints: 10 end point, 4 centre point, 3 horizontal, 2 coincident, 2 parallel, 2 point on line, 1 midpoint, 1 perpendicular, 4 other
  measures "d205" distance of L3.end L2.end
  measures "d206" distance of L2.end L1.end
  measures "d208" diameter of A0
  measures "d209" diameter of A1
  measures "d212" distance of A0.centre A2.centre
  measures "d403" distance from line of L5.start L2
  measures "d404" distance from line of L0.end L1
  measures "d405" distance from line of L5.end L0
extrude "Extrusion4" cut sketch "Sketch2" against normal through all contours A0 L2 L3 | L3 L2 A0 | A1 L2 L1 | L1 L2 A1 | A2 | A3
sketch "Sketch3" plane through (0, 7, 0) normal (0, 1, 0) x (1, 0, 0)
  line L0 (344.7411, -371) -> (344.7411, -321) construction
  line L1 (359.7411, -371) -> (359.7411, -321)
  line L2 (329.7411, -321) -> (329.7411, -371)
  arc A0 (329.7411, -371) -> (359.7411, -371) centre (344.7411, -371) ccw
  arc A1 (359.7411, -321) -> (329.7411, -321) centre (344.7411, -321) ccw
  line L3 (-449, -426) -> (449, -426) projected
  point P0 (0, 0)
  point P1 (344.7411, -346)
  dimension "d408" = 50
  dimension "d409" = 80
  dimension "d410" = 15
  constraints: 8 end point, 4 point on circle, 4 tangent, 2 centre point, 1 midpoint, 1 parallel, 1 vertical
  measures "d408" distance of L0.start L0.end
  measures "d409" distance from line of L3 point (344.741, -346)
  measures "d410" radius of A0
extrude "Extrusion5" cut sketch "Sketch3" against normal through all
sketch "Sketch4" plane through (0, 7, 0) normal (0, 1, 0) x (1, 0, 0)
  line L0 (258, -10) -> (115, -10) projected
  line L1 (115, 10) -> (258, 10) projected
  arc A0 (258, -10) -> (258, 10) centre (258, 0) ccw projected
  arc A1 (115, 10) -> (115, -10) centre (115, 0) ccw projected
  line L2 (107, -25) -> (266, -25)
  line L3 (268, -23) -> (268, 23)
  line L4 (266, 25) -> (107, 25)
  line L5 (105, 23) -> (105, -23)
  line L6 (105, -25) -> (268, 25) construction
  line L7 (268, -25) -> (105, 25) construction
  arc A2 (105, -23) -> (107, -25) centre (107, -23) ccw
  arc A3 (107, 25) -> (105, 23) centre (107, 23) ccw
  arc A4 (266, -25) -> (268, -23) centre (266, -23) ccw
  arc A5 (268, 23) -> (266, 25) centre (266, 23) ccw
  point P0 (0, 0)
  point P1 (186.5, 0)
  point P2 (186.5, 0)
  point P3 (186.5, 10)
  point P4 (105, 0)
  dimension "d411" = 50
  dimension "d412" = 163
  dimension "d415" = 2
  constraints: 12 end point, 9 point on circle, 8 point on line, 8 tangent, 5 midpoint, 4 centre point, 3 equal radius, 2 parallel, 1 perpendicular, 1 vertical alignment
  measures "d411" distance of L6.end L7.start
  measures "d412" distance of L6.end L7.end
  measures "d415" radius of A2
extrude "Extrusion6" cut sketch "Sketch4" against normal blind 10
sketch "Sketch5" plane through (0, 7, 0) normal (0, 1, 0) x (1, 0, 0)
  line L0 (105, -23) -> (105, 23) projected
  arc A0 (107, 25) -> (105, 23) centre (107, 23) ccw projected
  line L1 (107, 25) -> (266, 25) projected
  arc A1 (268, 23) -> (266, 25) centre (266, 23) ccw projected
  line L2 (268, 23) -> (268, -23) projected
  arc A2 (266, -25) -> (268, -23) centre (266, -23) ccw projected
  line L3 (266, -25) -> (107, -25) projected
  arc A3 (105, -23) -> (107, -25) centre (107, -23) ccw projected
  circle A4 centre (354.8, 16) radius 2.9 projected
  circle A5 centre (354.8, -16) radius 2.9 projected
  arc A6 (-456, -419) -> (-449, -426) centre (-449, -419) ccw projected
  line L4 (-449, -426) -> (449, -426) projected
  arc A7 (449, -426) -> (456, -419) centre (449, -419) ccw projected
  line L5 (456, -419) -> (456, 219) projected
  arc A8 (456, 219) -> (449, 226) centre (449, 219) ccw projected
  line L6 (449, 226) -> (-449, 226) projected
  arc A9 (-449, 226) -> (-456, 219) centre (-449, 219) ccw projected
  line L7 (-456, 219) -> (-456, -419) projected
  line L8 (201, -276) -> (204, -276) projected
  line L9 (204, -276) -> (204, -296) projected
  line L10 (204, -296) -> (201, -296) projected
  line L11 (201, -296) -> (201, -276) projected
  line L12 (-426, -316) -> (-423, -316) projected
  line L13 (-423, -316) -> (-423, -336) projected
  line L14 (-423, -336) -> (-426, -336) projected
  line L15 (-426, -336) -> (-426, -316) projected
  line L16 (9, -396) -> (9, -393) projected
  line L17 (9, -393) -> (57, -393) projected
  line L18 (57, -393) -> (57, -396) projected
  line L19 (57, -396) -> (9, -396) projected
  line L20 (-39, -256) -> (-39, -259) projected
  line L21 (-39, -259) -> (-87, -259) projected
  line L22 (-87, -259) -> (-87, -256) projected
  line L23 (-87, -256) -> (-39, -256) projected
  circle A10 centre (-67, 43) radius 2.5 projected
  circle A11 centre (-130, 43) radius 2.5 projected
  line L24 (51.5, 68) -> (46.5, 68) projected
  line L25 (46.5, 68) -> (46.5, 71) projected
  line L26 (46.5, 71) -> (51.5, 71) projected
  line L27 (51.5, 71) -> (51.5, 68) projected
  line L28 (6, 53) -> (3, 53) projected
  line L29 (3, 53) -> (3, 63) projected
  line L30 (3, 63) -> (6, 63) projected
  line L31 (6, 63) -> (6, 53) projected
  line L32 (56.25, -48) -> (46.25, -48) projected
  line L33 (46.25, -48) -> (46.25, -45) projected
  line L34 (46.25, -45) -> (56.25, -45) projected
  line L35 (56.25, -45) -> (56.25, -48) projected
  line L36 (46.25, -81) -> (46.25, -78) projected
  line L37 (46.25, -78) -> (56.25, -78) projected
  line L38 (56.25, -78) -> (56.25, -81) projected
  line L39 (56.25, -81) -> (46.25, -81) projected
  line L40 (61, -134.5) -> (61, -119.5) projected
  line L41 (61, -119.5) -> (64, -119.5) projected
  line L42 (64, -119.5) -> (64, -134.5) projected
  line L43 (64, -134.5) -> (61, -134.5) projected
  arc A12 (-406.25, 176) -> (-406, 176.25) centre (-406.25, 176.25) ccw projected
  line L44 (-406.25, 176) -> (-425.75, 176) projected
  arc A13 (-426, 176.25) -> (-425.75, 176) centre (-425.75, 176.25) ccw projected
  line L45 (-426, 176.25) -> (-426, 195.75) projected
  arc A14 (-425.75, 196) -> (-426, 195.75) centre (-425.75, 195.75) ccw projected
  line L46 (-425.75, 196) -> (-406.25, 196) projected
  arc A15 (-406, 195.75) -> (-406.25, 196) centre (-406.25, 195.75) ccw projected
  line L47 (-406, 195.75) -> (-406, 176.25) projected
  line L48 (-25.75, 196) -> (-6.25, 196) projected
  arc A16 (-6, 195.75) -> (-6.25, 196) centre (-6.25, 195.75) ccw projected
  line L49 (-6, 195.75) -> (-6, 176.25) projected
  arc A17 (-6.25, 176) -> (-6, 176.25) centre (-6.25, 176.25) ccw projected
  line L50 (-6.25, 176) -> (-25.75, 176) projected
  arc A18 (-26, 176.25) -> (-25.75, 176) centre (-25.75, 176.25) ccw projected
  line L51 (-26, 176.25) -> (-26, 195.75) projected
  arc A19 (-25.75, 196) -> (-26, 195.75) centre (-25.75, 195.75) ccw projected
  line L52 (5.5, -233.9) -> (2.5, -233.9) projected
  arc A20 (2.5, -228.1) -> (2.5, -233.9) centre (2.5, -231) ccw projected
  line L53 (2.5, -228.1) -> (5.5, -228.1) projected
  arc A21 (5.5, -233.9) -> (5.5, -228.1) centre (5.5, -231) ccw projected
  line L54 (-394.5, 183.1) -> (-397.5, 183.1) projected
  arc A22 (-397.5, 188.9) -> (-397.5, 183.1) centre (-397.5, 186) ccw projected
  line L55 (-397.5, 188.9) -> (-394.5, 188.9) projected
  arc A23 (-394.5, 183.1) -> (-394.5, 188.9) centre (-394.5, 186) ccw projected
  line L56 (-25.75, -221) -> (-6.25, -221) projected
  arc A24 (-6, -221.25) -> (-6.25, -221) centre (-6.25, -221.25) ccw projected
  line L57 (-6, -221.25) -> (-6, -240.75) projected
  arc A25 (-6.25, -241) -> (-6, -240.75) centre (-6.25, -240.75) ccw projected
  line L58 (-6.25, -241) -> (-25.75, -241) projected
  arc A26 (-26, -240.75) -> (-25.75, -241) centre (-25.75, -240.75) ccw projected
  line L59 (-26, -240.75) -> (-26, -221.25) projected
  arc A27 (-25.75, -221) -> (-26, -221.25) centre (-25.75, -221.25) ccw projected
  line L60 (-394.5, -233.9) -> (-397.5, -233.9) projected
  arc A28 (-397.5, -228.1) -> (-397.5, -233.9) centre (-397.5, -231) ccw projected
  line L61 (-397.5, -228.1) -> (-394.5, -228.1) projected
  arc A29 (-394.5, -233.9) -> (-394.5, -228.1) centre (-394.5, -231) ccw projected
  line L62 (296, -196) -> (296.0285, -196) projected
  line L63 (396, -236.2955) -> (396, -276.2955) projected
  line L64 (396, -396) -> (296, -396) projected
  line L65 (296, -396) -> (296, -196) projected
  line L66 (46.25, -142) -> (56.25, -142) projected
  line L67 (56.25, -142) -> (56.25, -145) projected
  line L68 (56.25, -145) -> (46.25, -145) projected
  line L69 (46.25, -145) -> (46.25, -142) projected
  line L70 (61, -70.5) -> (61, -55.5) projected
  line L71 (61, -55.5) -> (64, -55.5) projected
  line L72 (64, -55.5) -> (64, -70.5) projected
  line L73 (64, -70.5) -> (61, -70.5) projected
  arc A30 (49, -110) -> (44, -105) centre (44, -110) ccw projected
  line L74 (49, -110) -> (49, -120) projected
  arc A31 (44, -125) -> (49, -120) centre (44, -120) ccw projected
  line L75 (44, -125) -> (24, -125) projected
  arc A32 (19, -120) -> (24, -125) centre (24, -120) ccw projected
  line L76 (19, -120) -> (19, -110) projected
  arc A33 (24, -105) -> (19, -110) centre (24, -110) ccw projected
  line L77 (24, -105) -> (44, -105) projected
  line L78 (56, 53) -> (56, 63) projected
  line L79 (56, 63) -> (59, 63) projected
  line L80 (59, 63) -> (59, 53) projected
  line L81 (59, 53) -> (56, 53) projected
  line L82 (25, 62) -> (37, 62) projected
  arc A34 (37, 54) -> (37, 62) centre (37, 58) ccw projected
  line L83 (37, 54) -> (25, 54) projected
  arc A35 (25, 62) -> (25, 54) centre (25, 58) ccw projected
  circle A36 centre (-193, 43) radius 2.5 projected
  circle A37 centre (-67, -88) radius 2.5 projected
  line L84 (-135, -256) -> (-135, -259) projected
  line L85 (-135, -259) -> (-183, -259) projected
  line L86 (-183, -259) -> (-183, -256) projected
  line L87 (-183, -256) -> (-135, -256) projected
  line L88 (105, -396) -> (105, -393) projected
  line L89 (105, -393) -> (153, -393) projected
  line L90 (153, -393) -> (153, -396) projected
  line L91 (153, -396) -> (105, -396) projected
  line L92 (-426, -356) -> (-423, -356) projected
  line L93 (-423, -356) -> (-423, -376) projected
  line L94 (-423, -376) -> (-426, -376) projected
  line L95 (-426, -376) -> (-426, -356) projected
  line L96 (201, -316) -> (204, -316) projected
  line L97 (204, -316) -> (204, -336) projected
  line L98 (204, -336) -> (201, -336) projected
  line L99 (201, -336) -> (201, -316) projected
  line L100 (-279, -396) -> (-279, -393) projected
  line L101 (-279, -393) -> (-231, -393) projected
  line L102 (-231, -393) -> (-231, -396) projected
  line L103 (-231, -396) -> (-279, -396) projected
  line L104 (-426, -276) -> (-423, -276) projected
  line L105 (-423, -276) -> (-423, -296) projected
  line L106 (-423, -296) -> (-426, -296) projected
  line L107 (-426, -296) -> (-426, -276) projected
  line L108 (-87, -396) -> (-87, -393) projected
  line L109 (-87, -393) -> (-39, -393) projected
  line L110 (-39, -393) -> (-39, -396) projected
  line L111 (-39, -396) -> (-87, -396) projected
  line L112 (57, -256) -> (57, -259) projected
  line L113 (57, -259) -> (9, -259) projected
  line L114 (9, -259) -> (9, -256) projected
  line L115 (9, -256) -> (57, -256) projected
  line L116 (-327, -256) -> (-327, -259) projected
  line L117 (-327, -259) -> (-375, -259) projected
  line L118 (-375, -259) -> (-375, -256) projected
  line L119 (-375, -256) -> (-327, -256) projected
  circle A38 centre (-130, -88) radius 2.5 projected
  line L120 (46.5, 48) -> (51.5, 48) projected
  line L121 (51.5, 48) -> (51.5, 45) projected
  line L122 (51.5, 45) -> (46.5, 45) projected
  line L123 (46.5, 45) -> (46.5, 48) projected
  line L124 (10.5, 48) -> (15.5, 48) projected
  line L125 (15.5, 48) -> (15.5, 45) projected
  line L126 (15.5, 45) -> (10.5, 45) projected
  line L127 (10.5, 45) -> (10.5, 48) projected
  circle A39 centre (27.09, -53.5) radius 1.25 projected
  line L128 (21.75, -48) -> (11.75, -48) projected
  line L129 (11.75, -48) -> (11.75, -45) projected
  line L130 (11.75, -45) -> (21.75, -45) projected
  line L131 (21.75, -45) -> (21.75, -48) projected
  line L132 (11.75, -81) -> (11.75, -78) projected
  line L133 (11.75, -78) -> (21.75, -78) projected
  line L134 (21.75, -78) -> (21.75, -81) projected
  line L135 (21.75, -81) -> (11.75, -81) projected
  line L136 (7, -119.5) -> (7, -134.5) projected
  line L137 (7, -134.5) -> (4, -134.5) projected
  line L138 (4, -134.5) -> (4, -119.5) projected
  line L139 (4, -119.5) -> (7, -119.5) projected
  line L140 (-425.75, -221) -> (-406.25, -221) projected
  arc A40 (-406, -221.25) -> (-406.25, -221) centre (-406.25, -221.25) ccw projected
  line L141 (-406, -221.25) -> (-406, -240.75) projected
  arc A41 (-406.25, -241) -> (-406, -240.75) centre (-406.25, -240.75) ccw projected
  line L142 (-406.25, -241) -> (-425.75, -241) projected
  arc A42 (-426, -240.75) -> (-425.75, -241) centre (-425.75, -240.75) ccw projected
  line L143 (-426, -240.75) -> (-426, -221.25) projected
  arc A43 (-425.75, -221) -> (-426, -221.25) centre (-425.75, -221.25) ccw projected
  arc A44 (-37.5, 188.9) -> (-37.5, 183.1) centre (-37.5, 186) ccw projected
  line L144 (-37.5, 188.9) -> (-34.5, 188.9) projected
  arc A45 (-34.5, 183.1) -> (-34.5, 188.9) centre (-34.5, 186) ccw projected
  line L145 (-34.5, 183.1) -> (-37.5, 183.1) projected
  arc A46 (-37.5, -228.1) -> (-37.5, -233.9) centre (-37.5, -231) ccw projected
  line L146 (-37.5, -228.1) -> (-34.5, -228.1) projected
  arc A47 (-34.5, -233.9) -> (-34.5, -228.1) centre (-34.5, -231) ccw projected
  line L147 (-34.5, -233.9) -> (-37.5, -233.9) projected
  arc A48 (-437.5, 188.9) -> (-437.5, 183.1) centre (-437.5, 186) ccw projected
  line L148 (-437.5, 188.9) -> (-434.5, 188.9) projected
  arc A49 (-434.5, 183.1) -> (-434.5, 188.9) centre (-434.5, 186) ccw projected
  line L149 (-434.5, 183.1) -> (-437.5, 183.1) projected
  line L150 (5.5, 183.1) -> (2.5, 183.1) projected
  arc A50 (2.5, 188.9) -> (2.5, 183.1) centre (2.5, 186) ccw projected
  line L151 (2.5, 188.9) -> (5.5, 188.9) projected
  arc A51 (5.5, 183.1) -> (5.5, 188.9) centre (5.5, 186) ccw projected
  arc A52 (-437.5, -228.1) -> (-437.5, -233.9) centre (-437.5, -231) ccw projected
  line L152 (-437.5, -228.1) -> (-434.5, -228.1) projected
  arc A53 (-434.5, -233.9) -> (-434.5, -228.1) centre (-434.5, -231) ccw projected
  line L153 (-434.5, -233.9) -> (-437.5, -233.9) projected
  line L154 (11.75, -142) -> (21.75, -142) projected
  line L155 (21.75, -142) -> (21.75, -145) projected
  line L156 (21.75, -145) -> (11.75, -145) projected
  line L157 (11.75, -145) -> (11.75, -142) projected
  line L158 (7, -55.5) -> (7, -70.5) projected
  line L159 (7, -70.5) -> (4, -70.5) projected
  line L160 (4, -70.5) -> (4, -55.5) projected
  line L161 (4, -55.5) -> (7, -55.5) projected
  circle A54 centre (40.91, -53.5) radius 1.25 projected
  line L162 (29, 48) -> (29, 51) projected
  line L163 (29, 51) -> (33, 51) projected
  line L164 (33, 51) -> (33, 48) projected
  line L165 (33, 48) -> (29, 48) projected
  line L166 (15.5, 68) -> (10.5, 68) projected
  line L167 (10.5, 68) -> (10.5, 71) projected
  line L168 (10.5, 71) -> (15.5, 71) projected
  line L169 (15.5, 71) -> (15.5, 68) projected
  circle A55 centre (-193, -88) radius 2.5 projected
  line L170 (-231, -256) -> (-231, -259) projected
  line L171 (-231, -259) -> (-279, -259) projected
  line L172 (-279, -259) -> (-279, -256) projected
  line L173 (-279, -256) -> (-231, -256) projected
  line L174 (153, -256) -> (153, -259) projected
  line L175 (153, -259) -> (105, -259) projected
  line L176 (105, -259) -> (105, -256) projected
  line L177 (105, -256) -> (153, -256) projected
  line L178 (-183, -396) -> (-183, -393) projected
  line L179 (-183, -393) -> (-135, -393) projected
  line L180 (-135, -393) -> (-135, -396) projected
  line L181 (-135, -396) -> (-183, -396) projected
  line L182 (201, -356) -> (204, -356) projected
  line L183 (204, -356) -> (204, -376) projected
  line L184 (204, -376) -> (201, -376) projected
  line L185 (201, -376) -> (201, -356) projected
  line L186 (-375, -396) -> (-375, -393) projected
  line L187 (-375, -393) -> (-327, -393) projected
  line L188 (-327, -393) -> (-327, -396) projected
  line L189 (-327, -396) -> (-375, -396) projected
  line L190 (204, -256) -> (-426, -256)
  line L191 (-426, -256) -> (-426, -396)
  line L192 (-426, -396) -> (204, -396)
  line L193 (204, -396) -> (204, -256)
  line L194 (164, -286) -> (164, -366) construction
  line L195 (151.5, -286) -> (151.5, -366)
  line L196 (176.5, -366) -> (176.5, -286)
  arc A56 (176.5, -286) -> (151.5, -286) centre (164, -286) ccw
  arc A57 (151.5, -366) -> (176.5, -366) centre (164, -366) ccw
  line L197 (204, -316) -> (204, -336) projected
  line L198 (-376, -296) -> (-76, -296) construction
  line L199 (-376, -308.5) -> (-76, -308.5)
  line L200 (-76, -283.5) -> (-376, -283.5)
  arc A58 (-376, -283.5) -> (-376, -308.5) centre (-376, -296) ccw
  arc A59 (-76, -308.5) -> (-76, -283.5) centre (-76, -296) ccw
  line L201 (296.0285, -196) -> (296.0285, -236.2955) projected
  line L202 (296.0285, -236.2955) -> (299, -236.2955) projected
  line L203 (299, -236.2955) -> (299, -276.2955) projected
  line L204 (299, -276.2955) -> (296.0285, -276.2955) projected
  line L205 (296.0285, -276.2955) -> (296.0285, -316.5955) projected
  line L206 (296.0285, -316.5955) -> (299, -316.5955) projected
  line L207 (299, -316.5955) -> (299, -356.5955) projected
  line L208 (299, -356.5955) -> (296.0285, -356.5955) projected
  line L209 (296.0285, -356.5955) -> (296.0285, -395.9955) projected
  line L210 (296.0285, -395.9955) -> (299.0285, -395.9955) projected
  line L211 (299.0285, -395.9955) -> (299.0285, -393) projected
  line L212 (299.0285, -393) -> (312.7285, -393) projected
  line L213 (312.7285, -393) -> (312.7285, -395.9955) projected
  line L214 (312.7285, -395.9955) -> (353.0285, -395.9955) projected
  line L215 (353.0285, -395.9955) -> (353.0285, -393) projected
  line L216 (353.0285, -393) -> (393, -393) projected
  line L217 (393, -393) -> (393, -199) projected
  line L218 (393, -199) -> (299.0285, -199) projected
  line L219 (299.0285, -199) -> (299.0285, -196) projected
  line L220 (299.0285, -196) -> (312.7285, -196) projected
  line L221 (312.7285, -196) -> (312.7285, -198.9955) projected
  line L222 (312.7285, -198.9955) -> (353.0285, -198.9955) projected
  line L223 (353.0285, -198.9955) -> (353.0285, -196) projected
  line L224 (353.0285, -196) -> (393.0285, -196) projected
  line L225 (393.0285, -196) -> (393.0285, -236.2955) projected
  line L226 (393.0285, -236.2955) -> (396, -236.2955) projected
  line L227 (396, -276.2955) -> (393.0285, -276.2955) projected
  line L228 (393.0285, -276.2955) -> (393.0285, -316.5955) projected
  line L229 (393.0285, -316.5955) -> (396, -316.5955) projected
  line L230 (396, -316.5955) -> (396, -356.5955) projected
  line L231 (396, -356.5955) -> (393.0285, -356.5955) projected
  line L232 (393.0285, -356.5955) -> (393.0285, -395.9955) projected
  line L233 (393.0285, -395.9955) -> (396, -395.9955) projected
  line L234 (396, -395.9955) -> (396, -396) projected
  point P0 (129, -396)
  point P1 (129, -256)
  point P2 (204, -286)
  point P3 (-426, -286)
  point P4 (204, -326)
  point P5 (164, -326)
  point P6 (204, -326)
  point P7 (204, -326)
  point P8 (-226, -296)
  dimension "d492" = 25
  dimension "d493" = 40
  dimension "d494" = 80
  dimension "d495" = 300
  dimension "d496" = 25
  dimension "d497" = 40
  dimension "d498" = 200
  constraints: 24 end point, 9 midpoint, 8 point on circle, 8 tangent, 4 centre point, 4 parallel, 3 horizontal alignment, 2 horizontal, 2 vertical alignment, 1 perpendicular, 1 vertical
  measures "d492" diameter of A57
  measures "d493" distance from line of point (204, -326) L194
  measures "d494" distance of L194.start L194.end
  measures "d495" distance of L198.start L198.end
  measures "d496" diameter of A59
  measures "d497" distance between parallel lines of L190 L198
  measures "d498" distance from line of point (-226, -296) L191
extrude "Extrusion7" cut sketch "Sketch5" against normal through all contours A56 L196 A57 L195 | A58 L200 A59 L199